Autodesk Fusion 360 part; units mm, degrees
(part 7 of 18)
  line L4515 (124.885, -161.567) -> (124.972, -160.979)
  line L4516 (94.6766, -145.28) -> (94.0926, -145.3)
  line L4517 (89.7724, -175.689) -> (90.2951, -175.428)
  line L4518 (102.659, -180.778) -> (102.827, -181.338)
  line L4519 (124.855, -158.18) -> (124.719, -157.602)
  line L4520 (95.4301, -127.302) -> (96.0047, -127.408)
  line L4521 (125.032, -183.65) -> (125.012, -183.057)
  line L4522 (100.823, -142.282) -> (100.42, -142.705)
  line L4523 (85.8482, -132.483) -> (86.1085, -131.96)
  line L4524 (101.544, -188.763) -> (101.199, -189.234)
  line L4525 (124.719, -157.602) -> (124.544, -157.035)
  line L4526 (99.6734, -129.138) -> (100.121, -129.514)
  line L4527 (102.957, -181.908) -> (103.051, -182.484)
  line L4528 (114.861, -192.522) -> (115.452, -192.583)
  line L4529 (86.402, -131.454) -> (86.7274, -130.969)
  line L4530 (87.7561, -142.727) -> (87.3513, -142.306)
  line L4531 (94.2663, -174.602) -> (94.8498, -174.633)
  line L4532 (107.13, -184.025) -> (107.174, -184.617)
  line L4533 (87.3513, -142.306) -> (86.9746, -141.859)
  line L4534 (118.404, -192.396) -> (117.835, -192.528)
  line L4535 (99.6734, -176.538) -> (100.121, -176.914)
  line L4536 (107.033, -183.431) -> (107.035, -183.271)
  line L4537 (117.835, -192.528) -> (117.258, -192.623)
  line L4538 (107.38, -185.786) -> (107.541, -186.358)
  line L4539 (99.9903, -190.501) -> (99.5358, -190.868)
  line L4540 (123.133, -178.137) -> (122.753, -177.681)
  line L4541 (109.756, -166.427) -> (109.351, -166.006)
  line L4542 (108.627, -165.089) -> (108.311, -164.598)
  line L4543 (90.8336, -175.201) -> (91.3856, -175.009)
  line L4544 (120.044, -191.784) -> (119.511, -192.023)
  line L4545 (111.9, -175.729) -> (111.385, -176.023)
  line L4546 (112.578, -191.893) -> (113.132, -192.107)
  line L4547 (112.039, -191.643) -> (112.578, -191.893)
  line L4548 (116.046, -192.605) -> (116.639, -192.587)
  line L4549 (107.683, -180.529) -> (107.495, -181.092)
  line L4550 (123.801, -155.418) -> (123.483, -154.917)
  line L4551 (85.2769, -134.137) -> (85.4315, -133.574)
  line L4552 (120.446, -152.133) -> (119.918, -151.861)
  line L4553 (91.3856, -175.009) -> (91.9488, -174.854)
  line L4554 (124.972, -160.979) -> (125.021, -160.387)
  line L4555 (89.7724, -128.289) -> (90.2951, -128.028)
  line L4556 (107.909, -179.979) -> (107.683, -180.529)
  line L4557 (95.4301, -174.702) -> (96.0047, -174.808)
  line L4558 (110.889, -176.351) -> (110.417, -176.71)
  line L4559 (125.012, -183.057) -> (124.953, -182.466)
  line L4560 (95.8346, -145.128) -> (95.2581, -145.223)
  line L4561 (121.99, -190.501) -> (121.536, -190.868)
  line L4562 (89.6204, -144.127) -> (89.1214, -143.823)
  line L4563 (118.814, -151.424) -> (118.243, -151.261)
  line L4564 (116.677, -192.68) -> (116.093, -192.7)
  line L4565 (94.2663, -127.202) -> (94.8498, -127.233)
  line L4566 (124.855, -181.88) -> (124.719, -181.302)
  line L4567 (87.4688, -130.066) -> (87.8816, -129.653)
  line L4568 (86.7274, -178.369) -> (87.0836, -177.906)
  line L4569 (98.7108, -175.876) -> (99.2028, -176.192)
  line L4570 (86.402, -178.854) -> (86.7274, -178.369)
  line L4571 (102.389, -187.23) -> (102.14, -187.759)
  line L4572 (99.2028, -128.792) -> (99.6734, -129.138)
  line L4573 (86.7274, -130.969) -> (87.0836, -130.506)
  line L4574 (114.927, -192.627) -> (114.35, -192.534)
  line L4575 (122.753, -153.981) -> (122.342, -153.552)
  line L4576 (124.719, -181.302) -> (124.544, -180.735)
  line L4577 (100.938, -130.349) -> (101.304, -130.804)
  line L4578 (102.922, -185.562) -> (102.781, -186.129)
  line L4579 (109.157, -177.966) -> (108.795, -178.437)
  line L4580 (100.543, -177.318) -> (100.938, -177.749)
  line L4581 (108.311, -164.598) -> (108.028, -164.087)
  line L4582 (121.441, -152.779) -> (120.954, -152.44)
  line L4583 (85.1589, -182.11) -> (85.2769, -181.537)
  line L4584 (117.816, -192.434) -> (118.395, -192.3)
  line L4585 (121.441, -176.479) -> (120.954, -176.14)
  line L4586 (90.8336, -127.801) -> (91.3856, -127.609)
  line L4587 (100.121, -129.514) -> (100.543, -129.918)
  line L4588 (91.9488, -127.454) -> (92.5208, -127.335)
  line L4589 (87.8816, -177.053) -> (88.3203, -176.667)
  line L4590 (88.1873, -143.121) -> (87.7561, -142.727)
  line L4591 (107.258, -185.205) -> (107.38, -185.786)
  line L4592 (121.904, -176.851) -> (121.441, -176.479)
  line L4593 (124.885, -185.267) -> (124.972, -184.679)
  line L4594 (125.032, -159.95) -> (125.012, -159.357)
  line L4595 (119.918, -151.861) -> (119.373, -151.624)
  line L4596 (102.456, -132.831) -> (102.659, -133.378)
  line L4597 (122.823, -189.682) -> (122.42, -190.105)
  line L4598 (123.57, -188.553) -> (123.879, -188.046)
  line L4599 (101.641, -131.281) -> (101.946, -131.78)
  line L4600 (90.672, -144.635) -> (90.138, -144.398)
  line L4601 (123.879, -188.046) -> (124.153, -187.519)
  line L4602 (111.385, -176.023) -> (110.889, -176.351)
  line L4603 (88.643, -143.487) -> (88.1873, -143.121)
  line L4604 (108.55, -188.501) -> (108.888, -188.989)
  line L4605 (103.127, -136.25) -> (103.125, -136.424)
  line L4606 (102.218, -179.697) -> (102.456, -180.231)
  line L4607 (120.561, -191.511) -> (120.044, -191.784)
  line L4608 (124.594, -186.417) -> (124.758, -185.847)
  line L4609 (122.753, -177.681) -> (122.342, -177.252)
  line L4610 (124.084, -179.64) -> (123.801, -179.118)
  line L4611 (124.332, -156.48) -> (124.084, -155.94)
  line L4612 (111.018, -191.039) -> (111.518, -191.358)
  line L4613 (101.641, -178.681) -> (101.946, -179.18)
  line L4614 (98.7108, -128.476) -> (99.2028, -128.792)
  line L4615 (102.781, -138.729) -> (102.602, -139.286)
  line L4616 (114.35, -192.534) -> (113.78, -192.404)
  line L4617 (109.657, -166.193) -> (110.085, -166.605)
  line L4618 (113.132, -168.407) -> (113.699, -168.583)
  line L4619 (120.581, -191.39) -> (121.084, -191.074)
  line L4620 (85.2769, -181.537) -> (85.4315, -180.974)
  line L4621 (102.602, -139.286) -> (102.389, -139.83)
  line L4622 (108.311, -188.298) -> (108.028, -187.787)
  line L4623 (124.153, -163.819) -> (124.391, -163.276)
  line L4624 (86.1085, -179.36) -> (86.402, -178.854)
  line L4625 (117.23, -192.53) -> (117.816, -192.434)
  line L4626 (108.627, -188.789) -> (108.311, -188.298)
  line L4627 (107.777, -187.259) -> (107.562, -186.716)
  line L4628 (97.671, -127.944) -> (98.1995, -128.194)
  line L4629 (107.035, -183.271) -> (107.078, -182.688)
  line L4630 (117.258, -192.623) -> (116.677, -192.68)
  line L4631 (111.62, -191.527) -> (111.121, -191.223)
  line L4632 (90.2951, -128.028) -> (90.8336, -127.801)
  line L4633 (112.672, -192.035) -> (112.138, -191.798)
  line L4634 (121.084, -191.074) -> (121.565, -190.726)
  line L4635 (91.2202, -144.837) -> (90.672, -144.635)
  line L4636 (121.565, -190.726) -> (122.022, -190.347)
  line L4637 (88.7829, -128.91) -> (89.2676, -128.584)
  line L4638 (103.125, -183.824) -> (103.095, -184.407)
  line L4639 (34.9379, -82.9485) -> (35.3045, -83.4036)
  line L4640 (32.1995, -80.7936) -> (32.7108, -81.0764)
  line L4641 (33.6734, -81.738) -> (34.1207, -82.114)
  line L4642 (33.2028, -81.3917) -> (33.6734, -81.738)
  line L4643 (32.7108, -81.0764) -> (33.2028, -81.3917)
  line L4644 (34.1207, -82.114) -> (34.5428, -82.518)
  line L4645 (30.5713, -80.1506) -> (31.1275, -80.3297)
  line L4646 (31.671, -80.5443) -> (32.1995, -80.7936)
  line L4647 (31.1275, -80.3297) -> (31.671, -80.5443)
  line L4648 (34.5428, -82.518) -> (34.9379, -82.9485)
  line L4649 (21.4688, -82.6664) -> (21.8816, -82.2528)
  line L4650 (26.5208, -79.9348) -> (27.0994, -79.8529)
  line L4651 (24.2951, -80.628) -> (24.8336, -80.4011)
  line L4652 (23.7724, -80.8892) -> (24.2951, -80.628)
  line L4653 (23.2676, -81.1835) -> (23.7724, -80.8892)
  line L4654 (29.4301, -79.9018) -> (30.0047, -80.0077)
  line L4655 (20.7274, -83.569) -> (21.0836, -83.1057)
  line L4656 (25.3856, -80.2094) -> (25.9488, -80.0538)
  line L4657 (27.0994, -79.8529) -> (27.682, -79.8086)
  line L4658 (30.0047, -80.0077) -> (30.5713, -80.1506)
  line L4659 (28.8498, -79.8331) -> (29.4301, -79.9018)
  line L4660 (21.0836, -83.1057) -> (21.4688, -82.6664)
  line L4661 (21.8816, -82.2528) -> (22.3203, -81.8668)
  line L4662 (22.3203, -81.8668) -> (22.7829, -81.5099)
  line L4663 (28.2663, -79.802) -> (28.8498, -79.8331)
  line L4664 (22.7829, -81.5099) -> (23.2676, -81.1835)
  line L4665 (25.9488, -80.0538) -> (26.5208, -79.9348)
  line L4666 (24.8336, -80.4011) -> (25.3856, -80.2094)
  line L4667 (27.682, -79.8086) -> (28.2663, -79.802)
  line L4668 (25.7803, -97.6038) -> (25.2202, -97.4373)
  line L4669 (25.2202, -97.4373) -> (24.672, -97.2351)
  line L4670 (33.5358, -96.0681) -> (33.0587, -96.4054)
  line L4671 (32.5607, -96.7111) -> (32.0441, -96.9841)
  line L4672 (36.9575, -87.1077) -> (37.0514, -87.6844)
  line L4673 (28.6766, -97.8801) -> (28.0926, -97.9)
  line L4674 (36.6024, -91.8858) -> (36.3887, -92.4297)
  line L4675 (33.9903, -95.7008) -> (33.5358, -96.0681)
  line L4676 (37.1079, -88.266) -> (37.1268, -88.85)
  line L4677 (37.0514, -87.6844) -> (37.1079, -88.266)
  line L4678 (37.1268, -88.85) -> (37.1251, -89.0237)
  line L4679 (26.35, -97.7337) -> (25.7803, -97.6038)
  line L4680 (30.4039, -97.5957) -> (29.8346, -97.7276)
  line L4681 (34.42, -95.3049) -> (33.9903, -95.7008)
  line L4682 (24.672, -97.2351) -> (24.138, -96.9979)
  line L4683 (29.2581, -97.8226) -> (28.6766, -97.8801)
  line L4684 (36.1404, -92.9586) -> (35.8585, -93.4704)
  line L4685 (35.8585, -93.4704) -> (35.5441, -93.963)
  line L4686 (35.1986, -94.4342) -> (34.8234, -94.8821)
  line L4687 (24.138, -96.9979) -> (23.6204, -96.7267)
  line L4688 (36.3887, -92.4297) -> (36.1404, -92.9586)
  line L4689 (26.9269, -97.8266) -> (26.35, -97.7337)
  line L4690 (37.1251, -89.0237) -> (37.0951, -89.6073)
  line L4691 (23.1214, -96.4227) -> (22.643, -96.0871)
  line L4692 (23.6204, -96.7267) -> (23.1214, -96.4227)
  line L4693 (31.5109, -97.2231) -> (30.9634, -97.4273)
  line L4694 (37.0274, -90.1877) -> (36.9224, -90.7625)
  line L4695 (22.643, -96.0871) -> (22.1873, -95.7214)
  line L4696 (36.9224, -90.7625) -> (36.7806, -91.3293)
  line L4697 (37.0951, -89.6073) -> (37.0274, -90.1877)
  line L4698 (36.8266, -86.5382) -> (36.9575, -87.1077)
  line L4699 (22.1873, -95.7214) -> (21.7561, -95.327)
  line L4700 (21.7561, -95.327) -> (21.3513, -94.9056)
  line L4701 (36.7806, -91.3293) -> (36.6024, -91.8858)
  line L4702 (21.3513, -94.9056) -> (20.9746, -94.459)
  line L4703 (34.8234, -94.8821) -> (34.42, -95.3049)
  line L4704 (27.5085, -97.8821) -> (26.9269, -97.8266)
  line L4705 (35.5441, -93.963) -> (35.1986, -94.4342)
  line L4706 (36.2178, -84.8969) -> (36.4559, -85.4305)
  line L4707 (29.8346, -97.7276) -> (29.2581, -97.8226)
  line L4708 (35.3045, -83.4036) -> (35.6409, -83.8813)
  line L4709 (36.4559, -85.4305) -> (36.6591, -85.9784)
  line L4710 (32.0441, -96.9841) -> (31.5109, -97.2231)
  line L4711 (33.0587, -96.4054) -> (32.5607, -96.7111)
  line L4712 (30.9634, -97.4273) -> (30.4039, -97.5957)
  line L4713 (28.0926, -97.9) -> (27.5085, -97.8821)
  line L4714 (36.6591, -85.9784) -> (36.8266, -86.5382)
  line L4715 (35.6409, -83.8813) -> (35.9457, -84.3798)
  line L4716 (35.9457, -84.3798) -> (36.2178, -84.8969)
  line L4717 (53.1275, -151.43) -> (53.671, -151.644)
  line L4718 (41.0347, -159.571) -> (41.078, -158.988)
  line L4719 (41.541, -162.658) -> (41.7392, -163.217)
  line L4720 (48.2761, -168.722) -> (48.8615, -168.822)
  line L4721 (49.0994, -150.953) -> (49.682, -150.909)
  line L4722 (50.8498, -150.933) -> (51.4301, -151.002)
  line L4723 (49.682, -150.909) -> (50.2663, -150.902)
  line L4724 (50.0926, -169) -> (49.5085, -168.982)
  line L4725 (58.9224, -161.862) -> (58.7806, -162.429)
  line L4726 (48.5208, -151.035) -> (49.0994, -150.953)
  line L4727 (42.3113, -164.598) -> (42.0276, -164.087)
  line L4728 (44.539, -166.987) -> (45.0175, -167.339)
  line L4729 (50.2663, -150.902) -> (50.8498, -150.933)
  line L4730 (43.7561, -166.427) -> (43.3513, -166.006)
  line L4731 (55.9903, -166.801) -> (55.5358, -167.168)
  line L4732 (41.3817, -162.46) -> (41.2379, -161.893)
  line L4733 (48.35, -168.834) -> (47.7803, -168.704)
  line L4734 (56.42, -166.405) -> (55.9903, -166.801)
  line L4735 (41.1309, -161.319) -> (41.0612, -160.739)
  line L4736 (42.9746, -165.559) -> (42.6274, -165.089)
  line L4737 (59.1251, -160.124) -> (59.0951, -160.707)
  line L4738 (41.0332, -159.731) -> (41.0347, -159.571)
  line L4739 (47.7803, -168.704) -> (47.2202, -168.537)
  line L4740 (51.2581, -168.923) -> (50.6766, -168.98)
  line L4741 (41.1742, -160.917) -> (41.2578, -161.505)
  line L4742 (41.7774, -163.559) -> (41.5618, -163.016)
  line L4743 (47.6987, -168.583) -> (48.2761, -168.722)
  line L4744 (57.1986, -165.534) -> (56.8234, -165.982)
  line L4745 (52.3945, -168.6) -> (52.9627, -168.427)
  line L4746 (46.5778, -168.193) -> (47.1318, -168.407)
  line L4747 (58.3887, -163.53) -> (58.1404, -164.059)
  line L4748 (57.8585, -164.57) -> (57.5441, -165.063)
  line L4749 (52.5713, -151.251) -> (53.1275, -151.43)
  line L4750 (56.0223, -166.647) -> (56.453, -166.238)
  line L4751 (54.1995, -151.894) -> (54.7108, -152.176)
  line L4752 (53.671, -151.644) -> (54.1995, -151.894)
  line L4753 (58.9575, -158.208) -> (59.0514, -158.784)
  line L4754 (57.3045, -154.504) -> (57.6409, -154.981)
  line L4755 (59.1268, -159.95) -> (59.1251, -160.124)
  line L4756 (58.6591, -157.078) -> (58.8266, -157.638)
  line L4757 (56.1207, -153.214) -> (56.5428, -153.618)
  line L4758 (45.5183, -167.658) -> (46.0392, -167.943)
  line L4759 (53.5182, -168.217) -> (54.0585, -167.971)
  line L4760 (41.2379, -161.893) -> (41.1309, -161.319)
  line L4761 (41.2578, -161.505) -> (41.3803, -162.086)
  line L4762 (55.2028, -152.492) -> (55.6734, -152.838)
  line L4763 (50.6766, -168.98) -> (50.0926, -169)
  line L4764 (41.9741, -163.763) -> (42.2446, -164.291)
  line L4765 (55.5358, -167.168) -> (55.0587, -167.505)
  line L4766 (44.643, -167.187) -> (44.1873, -166.821)
  line L4767 (52.4039, -168.696) -> (51.8346, -168.828)
  line L4768 (55.0844, -167.374) -> (55.5654, -167.026)
  line L4769 (41.0291, -160.155) -> (41.0332, -159.731)
  line L4770 (59.0514, -158.784) -> (59.1079, -159.366)
  line L4771 (54.5813, -167.69) -> (55.0844, -167.374)
  line L4772 (56.8234, -165.982) -> (56.42, -166.405)
  line L4773 (45.0175, -167.339) -> (45.5183, -167.658)
  line L4774 (42.8876, -165.289) -> (43.2572, -165.754)
  line L4775 (57.9457, -155.48) -> (58.2178, -155.997)
  line L4776 (51.8162, -168.734) -> (52.3945, -168.6)
  line L4777 (42.6274, -165.089) -> (42.3113, -164.598)
  line L4778 (59.0274, -161.288) -> (58.9224, -161.862)
  line L4779 (41.3803, -162.086) -> (41.541, -162.658)
  line L4780 (47.1318, -168.407) -> (47.6987, -168.583)
  line L4781 (59.1079, -159.366) -> (59.1268, -159.95)
  line L4782 (46.0392, -167.943) -> (46.5778, -168.193)
  line L4783 (52.0047, -151.108) -> (52.5713, -151.251)
  line L4784 (55.0587, -167.505) -> (54.5607, -167.811)
  line L4785 (45.6204, -167.827) -> (45.1214, -167.523)
  line L4786 (43.6569, -166.193) -> (44.0847, -166.605)
  line L4787 (56.9379, -154.049) -> (57.3045, -154.504)
  line L4788 (55.5654, -167.026) -> (56.0223, -166.647)
  line L4789 (57.2286, -165.339) -> (57.57, -164.853)
  line L4790 (41.7392, -163.217) -> (41.9741, -163.763)
  line L4791 (56.8557, -165.801) -> (57.2286, -165.339)
  line L4792 (41.0612, -160.739) -> (41.0291, -160.155)
  line L4793 (42.5495, -164.801) -> (42.8876, -165.289)
  line L4794 (58.4559, -156.531) -> (58.6591, -157.078)
  line L4795 (43.2572, -165.754) -> (43.6569, -166.193)
  line L4796 (42.2446, -164.291) -> (42.5495, -164.801)
  line L4797 (44.1873, -166.821) -> (43.7561, -166.427)
  line L4798 (48.8615, -168.822) -> (49.4521, -168.883)
  line L4799 (48.9269, -168.927) -> (48.35, -168.834)
  line L4800 (46.138, -168.098) -> (45.6204, -167.827)
  line L4801 (58.6024, -162.986) -> (58.3887, -163.53)
  line L4802 (49.4521, -168.883) -> (50.0455, -168.905)
  line L4803 (49.5085, -168.982) -> (48.9269, -168.927)
  line L4804 (54.5607, -167.811) -> (54.0441, -168.084)
  line L4805 (54.0585, -167.971) -> (54.5813, -167.69)
  line L4806 (58.8266, -157.638) -> (58.9575, -158.208)
  line L4807 (56.5428, -153.618) -> (56.9379, -154.049)
  line L4808 (52.9634, -168.527) -> (52.4039, -168.696)
  line L4809 (43.3513, -166.006) -> (42.9746, -165.559)
  line L4810 (54.7108, -152.176) -> (55.2028, -152.492)
  line L4811 (58.2178, -155.997) -> (58.4559, -156.531)
  line L4812 (56.453, -166.238) -> (56.8557, -165.801)
  line L4813 (42.0276, -164.087) -> (41.7774, -163.559)
  line L4814 (55.6734, -152.838) -> (56.1207, -153.214)
  line L4815 (47.2202, -168.537) -> (46.672, -168.335)
  line L4816 (46.672, -168.335) -> (46.138, -168.098)
  line L4817 (58.1404, -164.059) -> (57.8585, -164.57)
  line L4818 (59.0951, -160.707) -> (59.0274, -161.288)
  line L4819 (50.0455, -168.905) -> (50.6391, -168.887)
  line L4820 (44.0847, -166.605) -> (44.539, -166.987)
  line L4821 (52.9627, -168.427) -> (53.5182, -168.217)
  line L4822 (54.0441, -168.084) -> (53.5109, -168.323)
  line L4823 (51.8346, -168.828) -> (51.2581, -168.923)
  line L4824 (57.6409, -154.981) -> (57.9457, -155.48)
  line L4825 (51.2302, -168.83) -> (51.8162, -168.734)
  line L4826 (45.1214, -167.523) -> (44.643, -167.187)
  line L4827 (47.9488, -151.154) -> (48.5208, -151.035)
  line L4828 (51.4301, -151.002) -> (52.0047, -151.108)
  line L4829 (41.5618, -163.016) -> (41.3817, -162.46)
  line L4830 (58.7806, -162.429) -> (58.6024, -162.986)
  line L4831 (57.5441, -165.063) -> (57.1986, -165.534)
  line L4832 (53.5109, -168.323) -> (52.9634, -168.527)
  line L4833 (50.6391, -168.887) -> (51.2302, -168.83)
  line L4834 (49.682, -174.609) -> (50.2663, -174.602)
  line L4835 (47.3856, -175.009) -> (47.9488, -174.854)
  line L4836 (80.3914, -186.976) -> (80.5935, -186.417)
  line L4837 (75.3734, -175.324) -> (74.8143, -175.124)
  line L4838 (79.57, -188.553) -> (79.8785, -188.046)
  line L4839 (76.954, -176.14) -> (76.4456, -175.833)
  line L4840 (66.8893, -176.351) -> (66.417, -176.71)
  line L4841 (81.0211, -184.087) -> (81.0318, -183.65)
  line L4842 (76.4456, -175.833) -> (75.9179, -175.561)
  line L4843 (68.9847, -175.246) -> (68.4345, -175.469)
  line L4844 (41.4315, -180.974) -> (41.6223, -180.422)
  line L4845 (74.8143, -175.124) -> (74.2432, -174.961)
  line L4846 (77.4411, -176.479) -> (76.954, -176.14)
  line L4847 (79.8785, -188.046) -> (80.1527, -187.519)
  line L4848 (63.9088, -179.979) -> (63.6834, -180.529)
  line L4849 (71.8893, -174.697) -> (71.2963, -174.729)
  line L4850 (43.8816, -177.053) -> (44.3203, -176.667)
  line L4851 (44.7829, -176.31) -> (45.2676, -175.984)
  line L4852 (45.2676, -175.984) -> (45.7724, -175.689)
  line L4853 (79.1334, -178.137) -> (78.7525, -177.681)
  line L4854 (77.5654, -190.726) -> (78.0223, -190.347)
  line L4855 (76.0585, -191.671) -> (76.5813, -191.39)
  line L4856 (66.417, -176.71) -> (65.9695, -177.101)
  line L4857 (80.1527, -187.519) -> (80.3914, -186.976)
  line L4858 (80.7582, -185.847) -> (80.8847, -185.267)
  line L4859 (77.9045, -176.851) -> (77.4411, -176.479)
  line L4860 (75.9179, -175.561) -> (75.3734, -175.324)
  line L4861 (64.17, -179.446) -> (63.9088, -179.979)
  line L4862 (73.075, -174.751) -> (72.483, -174.704)
  line L4863 (46.8336, -175.201) -> (47.3856, -175.009)
  line L4864 (65.9695, -177.101) -> (65.5489, -177.52)
  line L4865 (46.2951, -175.428) -> (46.8336, -175.201)
  line L4866 (74.9627, -192.127) -> (75.5182, -191.917)
  line L4867 (45.7724, -175.689) -> (46.2951, -175.428)
  line L4868 (80.5439, -180.735) -> (80.3321, -180.18)
  line L4869 (80.7185, -181.302) -> (80.5439, -180.735)
  line L4870 (80.8551, -181.88) -> (80.7185, -181.302)
  line L4871 (73.6626, -174.837) -> (73.075, -174.751)
  line L4872 (64.466, -178.931) -> (64.17, -179.446)
  line L4873 (80.9725, -184.679) -> (81.0211, -184.087)
  line L4874 (64.7955, -178.437) -> (64.466, -178.931)
  line L4875 (48.5208, -174.735) -> (49.0994, -174.653)
  line L4876 (72.483, -174.704) -> (71.8893, -174.697)
  line L4877 (41.6223, -180.422) -> (41.8482, -179.883)
  line L4878 (63.495, -181.092) -> (63.3443, -181.666)
  line L4879 (43.0836, -177.906) -> (43.4688, -177.466)
  line L4880 (49.0994, -174.653) -> (49.682, -174.609)
  line L4881 (43.4688, -177.466) -> (43.8816, -177.053)
  line L4882 (67.9003, -175.729) -> (67.3845, -176.023)
  line L4883 (50.2663, -174.602) -> (50.8498, -174.633)
  line L4884 (81.0318, -183.65) -> (81.0121, -183.057)
  line L4885 (41.2769, -181.537) -> (41.4315, -180.974)
  line L4886 (65.157, -177.966) -> (64.7955, -178.437)
  line L4887 (42.1085, -179.36) -> (42.402, -178.854)
  line L4888 (70.7068, -174.8) -> (70.1233, -174.911)
  line L4889 (65.5489, -177.52) -> (65.157, -177.966)
  line L4890 (79.8006, -179.118) -> (79.4833, -178.617)
  line L4891 (42.402, -178.854) -> (42.7274, -178.369)
  line L4892 (79.2286, -189.039) -> (79.57, -188.553)
  line L4893 (74.2432, -174.961) -> (73.6626, -174.837)
  line L4894 (80.5935, -186.417) -> (80.7582, -185.847)
  line L4895 (41.078, -182.688) -> (41.1589, -182.11)
  line L4896 (67.3845, -176.023) -> (66.8893, -176.351)
  line L4897 (63.232, -182.249) -> (63.1587, -182.838)
  line L4898 (81.0121, -183.057) -> (80.9531, -182.466)
  line L4899 (80.8847, -185.267) -> (80.9725, -184.679)
  line L4900 (74.3945, -192.3) -> (74.9627, -192.127)
  line L4901 (78.8557, -189.501) -> (79.2286, -189.039)
  line L4902 (78.453, -189.938) -> (78.8557, -189.501)
  line L4903 (63.1297, -184.025) -> (63.1742, -184.617)
  line L4904 (63.6834, -180.529) -> (63.495, -181.092)
  line L4905 (79.4833, -178.617) -> (79.1334, -178.137)
  line L4906 (41.1589, -182.11) -> (41.2769, -181.537)
  line L4907 (78.7525, -177.681) -> (78.3423, -177.252)
  line L4908 (78.3423, -177.252) -> (77.9045, -176.851)
  line L4909 (63.1587, -182.838) -> (63.1245, -183.431)
  line L4910 (75.5182, -191.917) -> (76.0585, -191.671)
  line L4911 (63.3443, -181.666) -> (63.232, -182.249)
  line L4912 (44.3203, -176.667) -> (44.7829, -176.31)
  line L4913 (80.9531, -182.466) -> (80.8551, -181.88)
  line L4914 (41.8482, -179.883) -> (42.1085, -179.36)
  line L4915 (76.5813, -191.39) -> (77.0844, -191.074)
  line L4916 (42.7274, -178.369) -> (43.0836, -177.906)
  line L4917 (47.9488, -174.854) -> (48.5208, -174.735)
  line L4918 (63.1245, -183.431) -> (63.1297, -184.025)
  line L4919 (77.0844, -191.074) -> (77.5654, -190.726)
  line L4920 (70.1233, -174.911) -> (69.5484, -175.059)
  line L4921 (71.2963, -174.729) -> (70.7068, -174.8)
  line L4922 (80.084, -179.64) -> (79.8006, -179.118)
  line L4923 (78.0223, -190.347) -> (78.453, -189.938)
  line L4924 (69.5484, -175.059) -> (68.9847, -175.246)
  line L4925 (68.4345, -175.469) -> (67.9003, -175.729)
  line L4926 (80.3321, -180.18) -> (80.084, -179.64)
  line L4927 (102.957, -63.4077) -> (103.051, -63.9844)
  line L4928 (51.6626, -56.3365) -> (51.075, -56.2508)
  line L4929 (88.1873, -72.0214) -> (87.7561, -71.627)
  line L4930 (99.5358, -72.3681) -> (99.0587, -72.7054)
  line L4931 (49.8893, -56.197) -> (49.2963, -56.2291)
  line L4932 (103.127, -65.15) -> (103.125, -65.3237)
  line L4933 (42.8876, -141.589) -> (43.2572, -142.054)
  line L4934 (89.6204, -73.0267) -> (89.1214, -72.7227)
  line L4935 (41.7392, -139.517) -> (41.9741, -140.063)
  line L4936 (100.121, -58.414) -> (100.543, -58.818)
  line L4937 (57.4833, -60.1165) -> (57.1334, -59.6368)
  line L4938 (90.672, -73.5351) -> (90.138, -73.2979)
  line L4939 (45.0175, -143.639) -> (45.5183, -143.958)
  line L4940 (52.8143, -56.6237) -> (52.2432, -56.461)
  line L4941 (42.6274, -141.389) -> (42.3113, -140.898)
  line L4942 (100.42, -71.6049) -> (99.9903, -72.0008)
  line L4943 (56.7525, -59.1812) -> (56.3423, -58.7519)
  line L4944 (50.6391, -145.187) -> (51.2302, -145.13)
  line L4945 (41.0291, -136.455) -> (41.0332, -136.031)
  line L4946 (41.541, -138.958) -> (41.7392, -139.517)
  line L4947 (41.0347, -135.871) -> (41.078, -135.288)
  line L4948 (41.3803, -138.386) -> (41.541, -138.958)
  line L4949 (98.0441, -73.2841) -> (97.5109, -73.5231)
  line L4950 (47.6987, -144.883) -> (48.2761, -145.022)
  line L4951 (44.643, -143.487) -> (44.1873, -143.121)
  line L4952 (41.9741, -140.063) -> (42.2446, -140.591)
  line L4953 (46.672, -144.635) -> (46.138, -144.398)
  line L4954 (94.6766, -74.1801) -> (94.0926, -74.2)
  line L4955 (43.3513, -142.306) -> (42.9746, -141.859)
  line L4956 (87.3513, -71.2056) -> (86.9746, -70.759)
  line L4957 (42.9746, -141.859) -> (42.6274, -141.389)
  line L4958 (102.922, -67.0625) -> (102.781, -67.6293)
  line L4959 (47.2202, -144.837) -> (46.672, -144.635)
  line L4960 (96.9634, -73.7273) -> (96.4039, -73.8957)
  line L4961 (58.5439, -62.2345) -> (58.3321, -61.6798)
  line L4962 (51.075, -56.2508) -> (50.483, -56.2042)
  line L4963 (46.4345, -56.9692) -> (45.9003, -57.2286)
  line L4964 (101.858, -69.7704) -> (101.544, -70.263)
  line L4965 (46.9847, -56.7458) -> (46.4345, -56.9692)
  line L4966 (91.7803, -73.9038) -> (91.2202, -73.7373)
  line L4967 (46.0392, -144.243) -> (46.5778, -144.493)
  line L4968 (103.125, -65.3237) -> (103.095, -65.9073)
  line L4969 (44.0847, -142.905) -> (44.539, -143.287)
  line L4970 (101.544, -70.263) -> (101.199, -70.7342)
  line L4971 (41.0332, -136.031) -> (41.0347, -135.871)
  line L4972 (103.108, -64.566) -> (103.127, -65.15)
  line L4973 (41.1742, -137.217) -> (41.2578, -137.805)
  line L4974 (102.389, -68.7297) -> (102.14, -69.2586)
  line L4975 (45.5183, -143.958) -> (46.0392, -144.243)
  line L4976 (101.199, -70.7342) -> (100.823, -71.1821)
  line L4977 (48.2761, -145.022) -> (48.8615, -145.122)
  line L4978 (49.2963, -56.2291) -> (48.7068, -56.3004)
  line L4979 (43.2572, -142.054) -> (43.6569, -142.493)
  line L4980 (97.5109, -73.5231) -> (96.9634, -73.7273)
  line L4981 (50.483, -56.2042) -> (49.8893, -56.197)
  line L4982 (93.5085, -74.1821) -> (92.9269, -74.1266)
  line L4983 (102.827, -62.8382) -> (102.957, -63.4077)
  line L4984 (103.051, -63.9844) -> (103.108, -64.566)
  line L4985 (94.0926, -74.2) -> (93.5085, -74.1821)
  line L4986 (100.938, -59.2485) -> (101.304, -59.7036)
  line L4987 (102.602, -68.1858) -> (102.389, -68.7297)
  line L4988 (46.138, -144.398) -> (45.6204, -144.127)
  line L4989 (55.9045, -58.3507) -> (55.4411, -57.9794)
  line L4990 (41.7774, -139.859) -> (41.5618, -139.316)
  line L4991 (54.4456, -57.333) -> (53.9179, -57.0606)
  line L4992 (42.5495, -141.101) -> (42.8876, -141.589)
  line L4993 (43.6569, -142.493) -> (44.0847, -142.905)
  line L4994 (103.095, -65.9073) -> (103.027, -66.4877)
  line L4995 (99.0587, -72.7054) -> (98.5607, -73.0111)
  line L4996 (100.823, -71.1821) -> (100.42, -71.6049)
  line L4997 (89.1214, -72.7227) -> (88.643, -72.3871)
  line L4998 (99.6734, -58.038) -> (100.121, -58.414)
  line L4999 (102.218, -61.1969) -> (102.456, -61.7305)
  line L5000 (54.954, -57.6397) -> (54.4456, -57.333)
  line L5001 (46.5778, -144.493) -> (47.1318, -144.707)
  line L5002 (47.5484, -56.5593) -> (46.9847, -56.7458)
  line L5003 (55.4411, -57.9794) -> (54.954, -57.6397)
  line L5004 (99.9903, -72.0008) -> (99.5358, -72.3681)
  line L5005 (90.138, -73.2979) -> (89.6204, -73.0267)
  line L5006 (102.781, -67.6293) -> (102.602, -68.1858)
  line L5007 (58.3321, -61.6798) -> (58.084, -61.1403)
  line L5008 (42.2446, -140.591) -> (42.5495, -141.101)
  line L5009 (41.2379, -138.193) -> (41.1309, -137.619)
  line L5010 (102.456, -61.7305) -> (102.659, -62.2784)
  line L5011 (48.1233, -56.4107) -> (47.5484, -56.5593)
  line L5012 (56.3423, -58.7519) -> (55.9045, -58.3507)
  line L5013 (48.7068, -56.3004) -> (48.1233, -56.4107)
  line L5014 (91.2202, -73.7373) -> (90.672, -73.5351)
  line L5015 (95.2581, -74.1226) -> (94.6766, -74.1801)
  line L5016 (86.6274, -70.289) -> (86.3113, -69.7975)
  line L5017 (102.659, -62.2784) -> (102.827, -62.8382)
  line L5018 (41.2578, -137.805) -> (41.3803, -138.386)
  line L5019 (41.3817, -138.76) -> (41.2379, -138.193)
  line L5020 (41.0612, -137.039) -> (41.0291, -136.455)
  line L5021 (45.1214, -143.823) -> (44.643, -143.487)
  line L5022 (101.304, -59.7036) -> (101.641, -60.1813)
  line L5023 (41.5618, -139.316) -> (41.3817, -138.76)
  line L5024 (43.7561, -142.727) -> (43.3513, -142.306)
  line L5025 (98.5607, -73.0111) -> (98.0441, -73.2841)
  line L5026 (49.4521, -145.183) -> (50.0455, -145.205)
  line L5027 (53.9179, -57.0606) -> (53.3734, -56.8239)
  line L5028 (47.1318, -144.707) -> (47.6987, -144.883)
  line L5029 (44.1873, -143.121) -> (43.7561, -142.727)
  line L5030 (42.0276, -140.387) -> (41.7774, -139.859)
  line L5031 (95.8346, -74.0276) -> (95.2581, -74.1226)
  line L5032 (92.35, -74.0337) -> (91.7803, -73.9038)
  line L5033 (50.0455, -145.205) -> (50.6391, -145.187)
  line L5034 (41.1309, -137.619) -> (41.0612, -137.039)
  line L5035 (52.2432, -56.461) -> (51.6626, -56.3365)
  line L5036 (42.3113, -140.898) -> (42.0276, -140.387)
  line L5037 (87.7561, -71.627) -> (87.3513, -71.2056)
  line L5038 (57.1334, -59.6368) -> (56.7525, -59.1812)
  line L5039 (100.543, -58.818) -> (100.938, -59.2485)
  line L5040 (103.027, -66.4877) -> (102.922, -67.0625)
  line L5041 (86.9746, -70.759) -> (86.6274, -70.289)
  line L5042 (48.8615, -145.122) -> (49.4521, -145.183)
  line L5043 (92.9269, -74.1266) -> (92.35, -74.0337)
  line L5044 (102.14, -69.2586) -> (101.858, -69.7704)
  line L5045 (96.4039, -73.8957) -> (95.8346, -74.0276)
  line L5046 (101.641, -60.1813) -> (101.946, -60.6798)
  line L5047 (58.084, -61.1403) -> (57.8006, -60.6185)
  line L5048 (88.643, -72.3871) -> (88.1873, -72.0214)
  line L5049 (44.539, -143.287) -> (45.0175, -143.639)
  line L5050 (101.946, -60.6798) -> (102.218, -61.1969)
  line L5051 (53.3734, -56.8239) -> (52.8143, -56.6237)
  line L5052 (57.8006, -60.6185) -> (57.4833, -60.1165)
  line L5053 (45.6204, -144.127) -> (45.1214, -143.823)
  line L5054 (75.671, -175.344) -> (76.1995, -175.594)
  line L5055 (100.753, -177.681) -> (100.342, -177.252)
  line L5056 (31.5109, -192.023) -> (30.9634, -192.227)
  line L5057 (20.2446, -187.991) -> (20.5495, -188.501)
  line L5058 (19.0291, -183.855) -> (19.0332, -183.431)
  line L5059 (36.1527, -187.519) -> (36.3914, -186.976)
  line L5060 (71.5085, -192.682) -> (70.9269, -192.627)
  line L5061 (29.2302, -192.53) -> (29.8162, -192.434)
  line L5062 (20.5495, -188.501) -> (20.8876, -188.989)
  line L5063 (78.42, -190.105) -> (77.9903, -190.501)
  line L5064 (85.2578, -185.205) -> (85.3803, -185.786)
  line L5065 (85.3803, -185.786) -> (85.541, -186.358)
  line L5066 (87.157, -177.966) -> (86.7955, -178.437)
  line L5067 (19.8482, -179.883) -> (20.1085, -179.36)
  line L5068 (85.0332, -183.431) -> (85.0347, -183.271)
  line L5069 (66.539, -190.687) -> (67.0175, -191.039)
  line L5070 (69.6987, -192.283) -> (70.2761, -192.422)
  line L5071 (69.7803, -192.404) -> (69.2202, -192.237)
  line L5072 (26.35, -192.534) -> (25.7803, -192.404)
  line L5073 (94.0926, -192.7) -> (93.5085, -192.682)
  line L5074 (23.6204, -191.527) -> (23.1214, -191.223)
  line L5075 (19.0347, -183.271) -> (19.078, -182.688)
  line L5076 (36.6024, -186.686) -> (36.3887, -187.23)
  line L5077 (36.9531, -182.466) -> (36.8551, -181.88)
  line L5078 (97.3734, -175.324) -> (96.8143, -175.124)
  line L5079 (96.2432, -174.961) -> (95.6626, -174.837)
  line L5080 (88.539, -190.687) -> (89.0175, -191.039)
  line L5081 (36.9725, -184.679) -> (37.0211, -184.087)
  line L5082 (37.0318, -183.65) -> (37.0121, -183.057)
  line L5083 (89.9003, -175.729) -> (89.3845, -176.023)
  line L5084 (30.9627, -192.127) -> (31.5182, -191.917)
  line L5085 (72.6391, -192.587) -> (73.2302, -192.53)
  line L5086 (78.1207, -176.914) -> (78.5428, -177.318)
  line L5087 (27.2963, -174.729) -> (26.7068, -174.8)
  line L5088 (22.1873, -190.521) -> (21.7561, -190.127)
  line L5089 (19.1245, -183.431) -> (19.1297, -184.025)
  line L5090 (32.0441, -191.784) -> (31.5109, -192.023)
  line L5091 (79.1986, -189.234) -> (78.8234, -189.682)
  line L5092 (21.6569, -189.893) -> (22.0847, -190.305)
  line L5093 (89.5183, -191.358) -> (90.0392, -191.643)
  line L5094 (64.402, -178.854) -> (64.7274, -178.369)
  line L5095 (73.4301, -174.702) -> (74.0047, -174.808)
  line L5096 (66.643, -190.887) -> (66.1873, -190.521)
  line L5097 (20.1085, -179.36) -> (20.402, -178.854)
  line L5098 (87.2572, -189.454) -> (87.6569, -189.893)
  line L5099 (32.4456, -175.833) -> (31.9179, -175.561)
  line L5100 (67.2676, -175.984) -> (67.7724, -175.689)
  line L5101 (89.0175, -191.039) -> (89.5183, -191.358)
  line L5102 (29.6626, -174.837) -> (29.075, -174.751)
  line L5103 (30.2432, -174.961) -> (29.6626, -174.837)
  line L5104 (78.5428, -177.318) -> (78.9379, -177.749)
  line L5105 (32.1995, -175.594) -> (32.7108, -175.876)
  line L5106 (70.8615, -192.522) -> (71.4521, -192.583)
  line L5107 (19.5618, -186.716) -> (19.3817, -186.16)
  line L5108 (98.0441, -191.784) -> (97.5109, -192.023)
  line L5109 (30.9634, -192.227) -> (30.4039, -192.396)
  line L5110 (74.4039, -192.396) -> (73.8346, -192.528)
  line L5111 (73.8162, -192.434) -> (74.3945, -192.3)
  line L5112 (76.1995, -175.594) -> (76.7108, -175.876)
  line L5113 (80.9575, -181.908) -> (81.0514, -182.484)
  line L5114 (29.8346, -192.528) -> (29.2581, -192.623)
  line L5115 (21.0836, -177.906) -> (21.4688, -177.466)
  line L5116 (77.2028, -176.192) -> (77.6734, -176.538)
  line L5117 (36.5935, -186.417) -> (36.7582, -185.847)
  line L5118 (94.6766, -192.68) -> (94.0926, -192.7)
  line L5119 (75.1275, -175.13) -> (75.671, -175.344)
  line L5120 (32.5607, -191.511) -> (32.0441, -191.784)
  line L5121 (36.8266, -181.338) -> (36.9575, -181.908)
  line L5122 (95.2581, -192.623) -> (94.6766, -192.68)
  line L5123 (93.5085, -192.682) -> (92.9269, -192.627)
  line L5124 (102.855, -181.88) -> (102.719, -181.302)
  line L5125 (63.0291, -183.855) -> (63.0332, -183.431)
  line L5126 (34.42, -190.105) -> (33.9903, -190.501)
  line L5127 (37.1079, -183.066) -> (37.1268, -183.65)
  line L5128 (102.544, -180.735) -> (102.332, -180.18)
  line L5129 (85.7392, -186.917) -> (85.9741, -187.463)
  line L5130 (69.3856, -175.009) -> (69.9488, -174.854)
  line L5131 (87.6569, -189.893) -> (88.0847, -190.305)
  line L5132 (36.3321, -180.18) -> (36.084, -179.64)
  line L5133 (71.0994, -174.653) -> (71.682, -174.609)
  line L5134 (85.2321, -182.249) -> (85.1587, -182.838)
  line L5135 (64.2446, -187.991) -> (64.5495, -188.501)
  line L5136 (86.8876, -188.989) -> (87.2572, -189.454)
  line L5137 (102.332, -180.18) -> (102.084, -179.64)
  line L5138 (70.35, -192.534) -> (69.7803, -192.404)
  line L5139 (65.4688, -177.466) -> (65.8816, -177.053)
  line L5140 (85.0291, -183.855) -> (85.0332, -183.431)
  line L5141 (19.1587, -182.838) -> (19.1245, -183.431)
  line L5142 (63.8482, -179.883) -> (64.1085, -179.36)
  line L5143 (71.682, -174.609) -> (72.2663, -174.602)
  line L5144 (24.2951, -175.428) -> (24.8336, -175.201)
  line L5145 (95.8346, -192.528) -> (95.2581, -192.623)
  line L5146 (72.6766, -192.68) -> (72.0926, -192.7)
  line L5147 (20.402, -178.854) -> (20.7274, -178.369)
  line L5148 (19.6222, -180.422) -> (19.8482, -179.883)
  line L5149 (63.6222, -180.422) -> (63.8482, -179.883)
  line L5150 (31.1275, -175.13) -> (31.671, -175.344)
  line L5151 (85.1742, -184.617) -> (85.2578, -185.205)
  line L5152 (34.3423, -177.252) -> (33.9045, -176.851)
  line L5153 (33.2028, -176.192) -> (33.6734, -176.538)
  line L5154 (88.0847, -190.305) -> (88.539, -190.687)
  line L5155 (36.7806, -186.129) -> (36.6024, -186.686)
  line L5156 (33.5654, -190.726) -> (34.0223, -190.347)
  line L5157 (37.0211, -184.087) -> (37.0318, -183.65)
  line L5158 (63.7392, -186.917) -> (63.9741, -187.463)
  line L5159 (26.2761, -192.422) -> (26.8615, -192.522)
  line L5160 (28.483, -174.704) -> (27.8893, -174.697)
  line L5161 (19.1309, -185.019) -> (19.0612, -184.439)
  line L5162 (19.078, -182.688) -> (19.1589, -182.11)
  line L5163 (88.8893, -176.351) -> (88.417, -176.71)
  line L5164 (67.1214, -191.223) -> (66.643, -190.887)
  line L5165 (66.0847, -190.305) -> (66.539, -190.687)
  line L5166 (72.0455, -192.605) -> (72.6391, -192.587)
  line L5167 (86.7955, -178.437) -> (86.466, -178.931)
  line L5168 (76.7108, -175.876) -> (77.2028, -176.192)
  line L5169 (32.7108, -175.876) -> (33.2028, -176.192)
  line L5170 (78.8234, -189.682) -> (78.42, -190.105)
  line L5171 (72.2663, -174.602) -> (72.8498, -174.633)
  line L5172 (96.9634, -192.227) -> (96.4039, -192.396)
  line L5173 (66.7829, -176.31) -> (67.2676, -175.984)
  line L5174 (101.801, -179.118) -> (101.483, -178.617)
  line L5175 (19.2379, -185.593) -> (19.1309, -185.019)
  line L5176 (81.1251, -183.824) -> (81.0951, -184.407)
  line L5177 (102.084, -179.64) -> (101.801, -179.118)
  line L5178 (97.5109, -192.023) -> (96.9634, -192.227)
  line L5179 (19.6834, -180.529) -> (19.495, -181.092)
  line L5180 (93.2963, -174.729) -> (92.7068, -174.8)
  line L5181 (22.417, -176.71) -> (21.9695, -177.101)
  line L5182 (28.0455, -192.605) -> (28.6391, -192.587)
  line L5183 (80.6024, -186.686) -> (80.3887, -187.23)
  line L5184 (27.4521, -192.583) -> (28.0455, -192.605)
  line L5185 (99.0587, -191.205) -> (98.5607, -191.511)
  line L5186 (101.483, -178.617) -> (101.133, -178.137)
  line L5187 (64.9746, -189.259) -> (64.6274, -188.789)
  line L5188 (32.5813, -191.39) -> (33.0844, -191.074)
  line L5189 (81.1079, -183.066) -> (81.1268, -183.65)
  line L5190 (37.0274, -184.988) -> (36.9224, -185.562)
  line L5191 (21.9695, -177.101) -> (21.5489, -177.52)
  line L5192 (70.2761, -192.422) -> (70.8615, -192.522)
  line L5193 (86.17, -179.446) -> (85.9088, -179.979)
  line L5194 (36.7582, -185.847) -> (36.8847, -185.267)
  line L5195 (102.719, -181.302) -> (102.544, -180.735)
  line L5196 (21.3513, -189.706) -> (20.9746, -189.259)
  line L5197 (73.2581, -192.623) -> (72.6766, -192.68)
  line L5198 (64.6274, -188.789) -> (64.3113, -188.298)
  line L5199 (94.0455, -192.605) -> (94.6391, -192.587)
  line L5200 (27.682, -174.609) -> (28.2663, -174.602)
  line L5201 (23.9003, -175.729) -> (23.3845, -176.023)
  line L5202 (85.1297, -184.025) -> (85.1742, -184.617)
  line L5203 (99.0844, -191.074) -> (99.5654, -190.726)
  line L5204 (34.5428, -177.318) -> (34.9379, -177.749)
  line L5205 (95.6626, -174.837) -> (95.075, -174.751)
  line L5206 (85.2379, -185.593) -> (85.1309, -185.019)
  line L5207 (24.138, -191.798) -> (23.6204, -191.527)
  line L5208 (37.0951, -184.407) -> (37.0274, -184.988)
  line L5209 (92.35, -192.534) -> (91.7803, -192.404)
  line L5210 (102.953, -182.466) -> (102.855, -181.88)
  line L5211 (19.2769, -181.537) -> (19.4315, -180.974)
  line L5212 (63.3803, -185.786) -> (63.541, -186.358)
  line L5213 (74.9634, -192.227) -> (74.4039, -192.396)
  line L5214 (35.5441, -188.763) -> (35.1986, -189.234)
  line L5215 (36.7185, -181.302) -> (36.5439, -180.735)
  line L5216 (33.0844, -191.074) -> (33.5654, -190.726)
  line L5217 (63.3817, -186.16) -> (63.2379, -185.593)
  line L5218 (79.5441, -188.763) -> (79.1986, -189.234)
  line L5219 (99.5654, -190.726) -> (100.022, -190.347)
  line L5220 (103.012, -183.057) -> (102.953, -182.466)
  line L5221 (86.0276, -187.787) -> (85.7774, -187.259)
  line L5222 (66.1873, -190.521) -> (65.7561, -190.127)
  line L5223 (19.0612, -184.439) -> (19.0291, -183.855)
  line L5224 (88.417, -176.71) -> (87.9695, -177.101)
  line L5225 (66.3203, -176.667) -> (66.7829, -176.31)
  line L5226 (68.0392, -191.643) -> (68.5778, -191.893)
  line L5227 (80.2178, -179.697) -> (80.4559, -180.231)
  line L5228 (73.8346, -192.528) -> (73.2581, -192.623)
  line L5229 (32.0585, -191.671) -> (32.5813, -191.39)
  line L5230 (65.8816, -177.053) -> (66.3203, -176.667)
  line L5231 (19.1589, -182.11) -> (19.2769, -181.537)
  line L5232 (28.6766, -192.68) -> (28.0926, -192.7)
  line L5233 (95.8162, -192.434) -> (96.3945, -192.3)
  line L5234 (67.6204, -191.527) -> (67.1214, -191.223)
  line L5235 (35.9457, -179.18) -> (36.2178, -179.697)
  line L5236 (72.8498, -174.633) -> (73.4301, -174.702)
  line L5237 (69.2202, -192.237) -> (68.672, -192.035)
  line L5238 (19.7774, -187.259) -> (19.5618, -186.716)
  line L5239 (80.1404, -187.759) -> (79.8585, -188.27)
  line L5240 (74.0047, -174.808) -> (74.5713, -174.951)
  line L5241 (34.453, -189.938) -> (34.8557, -189.501)
  line L5242 (25.1318, -192.107) -> (25.6987, -192.283)
  line L5243 (101.57, -188.553) -> (101.879, -188.046)
  line L5244 (85.9088, -179.979) -> (85.6834, -180.529)
  line L5245 (64.7274, -178.369) -> (65.0836, -177.906)
  line L5246 (101.879, -188.046) -> (102.153, -187.519)
  line L5247 (95.2302, -192.53) -> (95.8162, -192.434)
  line L5248 (22.0847, -190.305) -> (22.539, -190.687)
  line L5249 (63.1589, -182.11) -> (63.2769, -181.537)
  line L5250 (21.7561, -190.127) -> (21.3513, -189.706)
  line L5251 (87.9695, -177.101) -> (87.5489, -177.52)
  line L5252 (93.4521, -192.583) -> (94.0455, -192.605)
  line L5253 (67.0175, -191.039) -> (67.5183, -191.358)
  line L5254 (19.3803, -185.786) -> (19.541, -186.358)
  line L5255 (92.1233, -174.911) -> (91.5484, -175.059)
  line L5256 (20.466, -178.931) -> (20.17, -179.446)
  line L5257 (97.5182, -191.917) -> (98.0585, -191.671)
  line L5258 (85.9741, -187.463) -> (86.2446, -187.991)
  line L5259 (102.391, -186.976) -> (102.594, -186.417)
  line L5260 (79.3045, -178.204) -> (79.6409, -178.681)
  line L5261 (86.2446, -187.991) -> (86.5495, -188.501)
  line L5262 (35.1986, -189.234) -> (34.8234, -189.682)
  line L5263 (80.7806, -186.129) -> (80.6024, -186.686)
  line L5264 (22.3203, -176.667) -> (22.7829, -176.31)
  line L5265 (19.4315, -180.974) -> (19.6222, -180.422)
  line L5266 (64.8876, -188.989) -> (65.2572, -189.454)
  line L5267 (94.6391, -192.587) -> (95.2302, -192.53)
  line L5268 (80.8266, -181.338) -> (80.9575, -181.908)
  line L5269 (92.7068, -174.8) -> (92.1233, -174.911)
  line L5270 (77.6734, -176.538) -> (78.1207, -176.914)
  line L5271 (20.3113, -188.298) -> (20.0276, -187.787)
  line L5272 (21.4688, -177.466) -> (21.8816, -177.053)
  line L5273 (78.9379, -177.749) -> (79.3045, -178.204)
  line L5274 (23.1214, -191.223) -> (22.643, -190.887)
  line L5275 (92.2761, -192.422) -> (92.8615, -192.522)
  line L5276 (91.6987, -192.283) -> (92.2761, -192.422)
  line L5277 (19.9741, -187.463) -> (20.2446, -187.991)
  line L5278 (35.1334, -178.137) -> (34.7525, -177.681)
  line L5279 (23.7724, -175.689) -> (24.2951, -175.428)
  line L5280 (92.8615, -192.522) -> (93.4521, -192.583)
  line L5281 (26.7068, -174.8) -> (26.1233, -174.911)
  line L5282 (23.5183, -191.358) -> (24.0392, -191.643)
  line L5283 (85.1245, -183.431) -> (85.1297, -184.025)
  line L5284 (63.078, -182.688) -> (63.1589, -182.11)
  line L5285 (19.1297, -184.025) -> (19.1742, -184.617)
  line L5286 (24.9847, -175.246) -> (24.4345, -175.469)
  line L5287 (99.4411, -176.479) -> (98.954, -176.14)
  line L5288 (76.0441, -191.784) -> (75.5109, -192.023)
  line L5289 (29.2581, -192.623) -> (28.6766, -192.68)
  line L5290 (21.5489, -177.52) -> (21.157, -177.966)
  line L5291 (36.2178, -179.697) -> (36.4559, -180.231)
  line L5292 (86.6274, -188.789) -> (86.3113, -188.298)
  line L5293 (63.2578, -185.205) -> (63.3803, -185.786)
  line L5294 (37.0514, -182.484) -> (37.1079, -183.066)
  line L5295 (88.643, -190.887) -> (88.1873, -190.521)
  line L5296 (30.0047, -174.808) -> (30.5713, -174.951)
  line L5297 (99.9045, -176.851) -> (99.4411, -176.479)
  line L5298 (88.1873, -190.521) -> (87.7561, -190.127)
  line L5299 (33.9045, -176.851) -> (33.4411, -176.479)
  line L5300 (77.0587, -191.205) -> (76.5607, -191.511)
  line L5301 (77.9903, -190.501) -> (77.5358, -190.868)
  line L5302 (98.5813, -191.39) -> (99.0844, -191.074)
  line L5303 (36.9575, -181.908) -> (37.0514, -182.484)
  line L5304 (27.0994, -174.653) -> (27.682, -174.609)
  line L5305 (80.6591, -180.778) -> (80.8266, -181.338)
  line L5306 (20.7955, -178.437) -> (20.466, -178.931)
  line L5307 (19.495, -181.092) -> (19.3443, -181.666)
  line L5308 (19.2578, -185.205) -> (19.3803, -185.786)
  line L5309 (77.5358, -190.868) -> (77.0587, -191.205)
  line L5310 (72.0926, -192.7) -> (71.5085, -192.682)
  line L5311 (19.0332, -183.431) -> (19.0347, -183.271)
  line L5312 (91.5484, -175.059) -> (90.9847, -175.246)
  line L5313 (85.1309, -185.019) -> (85.0612, -184.439)
  line L5314 (101.229, -189.039) -> (101.57, -188.553)
  line L5315 (35.2286, -189.039) -> (35.57, -188.553)
  line L5316 (20.8876, -188.989) -> (21.2572, -189.454)
  line L5317 (87.7561, -190.127) -> (87.3513, -189.706)
  line L5318 (70.5208, -174.735) -> (71.0994, -174.653)
  line L5319 (65.0836, -177.906) -> (65.4688, -177.466)
  line L5320 (19.3817, -186.16) -> (19.2379, -185.593)
  line L5321 (31.5182, -191.917) -> (32.0585, -191.671)
  line L5322 (35.4833, -178.617) -> (35.1334, -178.137)
  line L5323 (37.0121, -183.057) -> (36.9531, -182.466)
  line L5324 (100.342, -177.252) -> (99.9045, -176.851)
  line L5325 (98.0585, -191.671) -> (98.5813, -191.39)
  line L5326 (30.4039, -192.396) -> (29.8346, -192.528)
  line L5327 (33.4411, -176.479) -> (32.954, -176.14)
  line L5328 (31.671, -175.344) -> (32.1995, -175.594)
  line L5329 (86.3113, -188.298) -> (86.0276, -187.787)
  line L5330 (85.0612, -184.439) -> (85.0291, -183.855)
  line L5331 (96.3945, -192.3) -> (96.9627, -192.127)
  line L5332 (36.084, -179.64) -> (35.8006, -179.118)
  line L5333 (85.3817, -186.16) -> (85.2379, -185.593)
  line L5334 (64.0276, -187.787) -> (63.7774, -187.259)
  line L5335 (34.9379, -177.749) -> (35.3045, -178.204)
  line L5336 (76.5607, -191.511) -> (76.0441, -191.784)
  line L5337 (23.3845, -176.023) -> (22.8893, -176.351)
  line L5338 (75.5109, -192.023) -> (74.9634, -192.227)
  line L5339 (96.9627, -192.127) -> (97.5182, -191.917)
  line L5340 (68.8336, -175.201) -> (69.3856, -175.009)
  line L5341 (69.9488, -174.854) -> (70.5208, -174.735)
  line L5342 (21.2572, -189.454) -> (21.6569, -189.893)
  line L5343 (98.954, -176.14) -> (98.4456, -175.833)
  line L5344 (97.9179, -175.561) -> (97.3734, -175.324)
  line L5345 (20.7274, -178.369) -> (21.0836, -177.906)
  line L5346 (63.2769, -181.537) -> (63.4315, -180.974)
  line L5347 (81.0514, -182.484) -> (81.1079, -183.066)
  line L5348 (36.3914, -186.976) -> (36.5935, -186.417)
  line L5349 (63.2379, -185.593) -> (63.1309, -185.019)
  line L5350 (68.2951, -175.428) -> (68.8336, -175.201)
  line L5351 (80.9224, -185.562) -> (80.7806, -186.129)
  line L5352 (37.1251, -183.824) -> (37.0951, -184.407)
  line L5353 (25.5484, -175.059) -> (24.9847, -175.246)
  line L5354 (26.5208, -174.735) -> (27.0994, -174.653)
  line L5355 (71.4521, -192.583) -> (72.0455, -192.605)
  line L5356 (33.6734, -176.538) -> (34.1207, -176.914)
  line L5357 (63.0347, -183.271) -> (63.078, -182.688)
  line L5358 (24.0392, -191.643) -> (24.5778, -191.893)
  line L5359 (63.0612, -184.439) -> (63.0291, -183.855)
  line L5360 (27.5085, -192.682) -> (26.9269, -192.627)
  line L5361 (23.0175, -191.039) -> (23.5183, -191.358)
  line L5362 (85.1587, -182.838) -> (85.1245, -183.431)
  line L5363 (69.1318, -192.107) -> (69.6987, -192.283)
  line L5364 (89.3845, -176.023) -> (88.8893, -176.351)
  line L5365 (28.8498, -174.633) -> (29.4301, -174.702)
  line L5366 (36.8551, -181.88) -> (36.7185, -181.302)
  line L5367 (96.4039, -192.396) -> (95.8346, -192.528)
  line L5368 (19.232, -182.249) -> (19.1587, -182.838)
  line L5369 (86.466, -178.931) -> (86.17, -179.446)
  line L5370 (22.7829, -176.31) -> (23.2676, -175.984)
  line L5371 (98.4456, -175.833) -> (97.9179, -175.561)
  line L5372 (35.8006, -179.118) -> (35.4833, -178.617)
  line L5373 (35.8785, -188.046) -> (36.1527, -187.519)
  line L5374 (86.9746, -189.259) -> (86.6274, -188.789)
  line L5375 (79.6409, -178.681) -> (79.9457, -179.18)
  line L5376 (102.594, -186.417) -> (102.758, -185.847)
  line L5377 (79.8585, -188.27) -> (79.5441, -188.763)
  line L5378 (63.541, -186.358) -> (63.7392, -186.917)
  line L5379 (95.075, -174.751) -> (94.483, -174.704)
  line L5380 (102.758, -185.847) -> (102.885, -185.267)
  line L5381 (26.9269, -192.627) -> (26.35, -192.534)
  line L5382 (25.2202, -192.237) -> (24.672, -192.035)
  line L5383 (91.2202, -192.237) -> (90.672, -192.035)
  line L5384 (31.9179, -175.561) -> (31.3734, -175.324)
  line L5385 (91.7803, -192.404) -> (91.2202, -192.237)
  line L5386 (27.8893, -174.697) -> (27.2963, -174.729)
  line L5387 (22.8893, -176.351) -> (22.417, -176.71)
  line L5388 (96.8143, -175.124) -> (96.2432, -174.961)
  line L5389 (80.3887, -187.23) -> (80.1404, -187.759)
  line L5390 (85.3443, -181.666) -> (85.2321, -182.249)
  line L5391 (85.6834, -180.529) -> (85.495, -181.092)
  line L5392 (35.3045, -178.204) -> (35.6409, -178.681)
  line L5393 (63.5618, -186.716) -> (63.3817, -186.16)
  line L5394 (89.1214, -191.223) -> (88.643, -190.887)
  line L5395 (19.1742, -184.617) -> (19.2578, -185.205)
  line L5396 (87.3513, -189.706) -> (86.9746, -189.259)
  line L5397 (36.9224, -185.562) -> (36.7806, -186.129)
  line L5398 (79.9457, -179.18) -> (80.2178, -179.697)
  line L5399 (102.153, -187.519) -> (102.391, -186.976)
  line L5400 (36.5439, -180.735) -> (36.3321, -180.18)
  line L5401 (103.032, -183.65) -> (103.012, -183.057)
  line L5402 (98.5607, -191.511) -> (98.0441, -191.784)
  line L5403 (21.8816, -177.053) -> (22.3203, -176.667)
  line L5404 (64.5495, -188.501) -> (64.8876, -188.989)
  line L5405 (103.021, -184.087) -> (103.032, -183.65)
  line L5406 (30.8143, -175.124) -> (30.2432, -174.961)
  line L5407 (81.0951, -184.407) -> (81.0274, -184.988)
  line L5408 (34.8234, -189.682) -> (34.42, -190.105)
  line L5409 (89.6204, -191.527) -> (89.1214, -191.223)
  line L5410 (33.0587, -191.205) -> (32.5607, -191.511)
  line L5411 (100.453, -189.938) -> (100.856, -189.501)
  line L5412 (102.885, -185.267) -> (102.972, -184.679)
  line L5413 (80.4559, -180.231) -> (80.6591, -180.778)